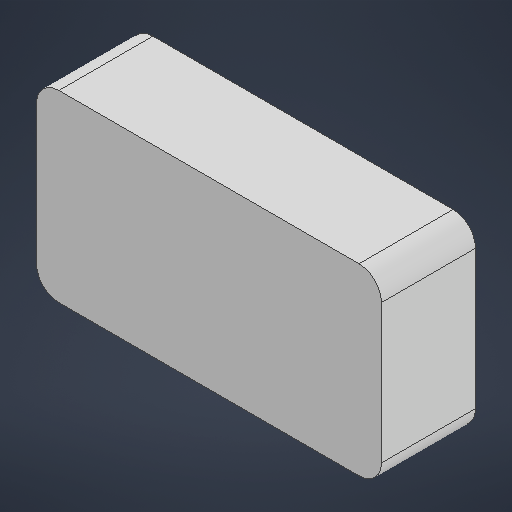
# Autodesk Inventor part: DUMMY-BATT
Saved by Autodesk Inventor 2027.1 (Build 311270010, 270A)
## iProperties
Created: 2026-10-28
Part Number: DUMMY-BATT
Material: Generic
Description: 2x18650 holder + cells
Document SubType Name: Modeling
Designer: shyan
Density: 1 g/cm^3
Appearance: Default
Mass: 110 g
Author: shyan
Autodesk Inventor part; units mm, degrees
ref_plane "YZ Plane" through (0, 0, 0) normal (1, 0, 0) x (0, 1, 0)
ref_plane "XZ Plane" through (0, 0, 0) normal (0, 1, 0) x (-1, 0, 0)
ref_plane "XY Plane" through (0, 0, 0) normal (0, 0, 1) x (1, 0, 0)
sketch "sk_body" plane through (0, 0, 0) normal (0, 0, 1) x (1, 0, 0)
  line L0 (-38.5, -20.5) -> (38.5, -20.5)
  line L1 (38.5, -20.5) -> (38.5, 20.5)
  line L2 (38.5, 20.5) -> (-38.5, 20.5)
  line L3 (-38.5, 20.5) -> (-38.5, -20.5)
  line L4 (-53.9, 0) -> (53.9, 0) construction
  line L5 (0, -28.7) -> (0, 28.7) construction
  point P0 (0, 0)
  dimension "d0" = 77
  dimension "d1" = 41
  constraints: 8 end point, 2 parallel, 1 horizontal, 1 perpendicular, 2 other
  measures "d0" distance of L0.start L0.end
  measures "d1" distance of L0.end L1.end
extrude "Body" add sketch "sk_body" along normal blind 21
fillet "CornerRadii" radius 5 4 edges at (-38.5, -20.5, 10.5) (-38.5, 20.5, 10.5) (38.5, 20.5, 10.5) (38.5, -20.5, 10.5)
equation "\"d0\" = bat_W"
equation "\"d1\" = bat_D"
equation "\"d2\" = bat_H"
equation "\"d4\" = bat_R"
equation "\"bat_W\" = 77"
equation "\"bat_D\" = 41"
equation "\"bat_H\" = 21"
equation "\"bat_R\" = 5"
body "Solid1"
